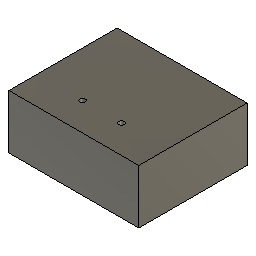
Motor Holder Block (Autodesk Fusion 360 design; units mm, degrees)
part number: 2026-01-13-20-57-45-598
Autodesk Fusion 360 part; units mm, degrees
sketch "Sketch1" plane through (0, 0, 0) normal (0, 0, 1) x (1, 0, 0)
  line L0 (-29.9701, 36.95) -> (30.0299, 36.95)
  line L1 (30.0299, 36.95) -> (30.0299, -13.05)
  line L2 (30.0299, -13.05) -> (-29.9701, -13.05)
  line L3 (-29.9701, -13.05) -> (-29.9701, 36.95)
  dimension "d1" = 50
  dimension "d2" = 60
  dimension "d17" = 13.05
  constraint horizontal L0
  constraint vertical L1
  constraint horizontal L2
  constraint vertical L3
  measures "d1" distance of L0.start L2.end
  measures "d2" distance of L0.start L0.end
  measures "d17" distance of origin L2
extrude "Extrude1" add sketch "Sketch1" along normal blind 25
sketch "Sketch2" plane through (0, 0, 25) normal (0, 0, 1) x (-1, 0, 0)
  line L0 (29.9701, 13.05) -> (-30.0299, 13.05)
  line L1 (-30.0299, 13.05) -> (-30.0299, -36.95)
  line L2 (-30.0299, -36.95) -> (29.9701, -36.95)
  line L3 (29.9701, -36.95) -> (29.9701, 13.05)
  line L4 (-10.3712, 2.375) -> (-11.7424, 0)
  line L5 (-11.7424, 0) -> (-10.3712, -2.375)
  line L6 (-10.3712, -2.375) -> (-7.6288, -2.375)
  line L7 (-7.6288, -2.375) -> (-6.2576, 0)
  line L8 (-6.2576, 0) -> (-7.6288, 2.375)
  line L9 (-7.6288, 2.375) -> (-10.3712, 2.375)
  line L10 (7.6288, 2.375) -> (6.2576, 0)
  line L11 (6.2576, 0) -> (7.6288, -2.375)
  line L12 (7.6288, -2.375) -> (10.3712, -2.375)
  line L13 (10.3712, -2.375) -> (11.7424, 0)
  line L14 (11.7424, 0) -> (10.3712, 2.375)
  line L15 (10.3712, 2.375) -> (7.6288, 2.375)
  line L16 (-9, 0) -> (9, 0)
  point P0 (-9, 0)
  point P1 (9, 0)
  point P2 (-9, 0)
  point P3 (9, 0)
  dimension "d11" = 4.75
  dimension "d12" = 4.75
  dimension "d13" = 18
  constraint coincident P2 P0
  constraint coincident P3 P1
  constraint horizontal origin L10.end
  constraint horizontal P2 P3
  constraint horizontal L7.end L10.end
  constraint midpoint origin L16
  measures "d11" distance of L6 L9
  measures "d12" distance of L12 L15
  measures "d13" distance of P2 P3
hole "Hole1" at (-9, 0, 25) at (9, 0, 25) direction (0, 0, -1) diameter 2.5 depth 12 tip angle 180
extrude "Extrude2" cut sketch "Sketch2" against normal blind 2 from surface at -3 contours L4 L5 L6 L7 L8 L9 | L10 L11 L12 L13 L14 L15
